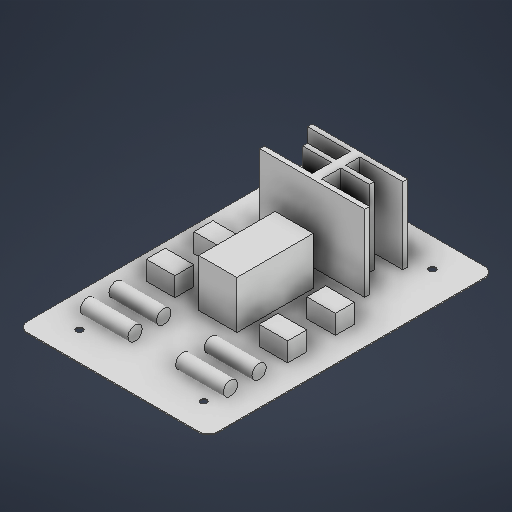
# Autodesk Inventor part: circuit_dummy
Saved by Autodesk Inventor 2027.1 (Build 311270010, 270A)
## iProperties
Created: 2026-10-24
Part Number: circuit_dummy
Material: Generic
Document SubType Name: Modeling
Designer: MSIPC
Density: 1 g/cm^3
Appearance: Default
Author: MSIPC
Autodesk Inventor part; units mm, degrees
ref_plane "YZ Plane" through (0, 0, 0) normal (1, 0, 0) x (0, 1, 0)
ref_plane "XZ Plane" through (0, 0, 0) normal (0, 1, 0) x (-1, 0, 0)
ref_plane "XY Plane" through (0, 0, 0) normal (0, 0, 1) x (1, 0, 0)
sketch "Sketch1" plane through (0, 0, 0) normal (0, 1, 0) x (-1, 0, 0)
  line L0 (-9, -15) -> (9, -15)
  line L1 (10, -14) -> (10, 14)
  line L2 (9, 15) -> (-9, 15)
  line L3 (-10, 14) -> (-10, -14)
  line L4 (-10, -15) -> (10, 15) construction
  line L5 (10, -15) -> (-10, 15) construction
  circle A0 centre (6.5, 12) radius 0.35
  line L6 (0, 0) -> (7.9497, 0)
  line L7 (0, 0) -> (0, 6.0781)
  circle A1 centre (6.5, -12) radius 0.35
  circle A2 centre (-6.5, 12) radius 0.35
  circle A3 centre (-6.5, -12) radius 0.35
  arc A4 (-9, 15) -> (-10, 14) centre (-9, 14) ccw
  arc A5 (10, 14) -> (9, 15) centre (9, 14) ccw
  arc A6 (9, -15) -> (10, -14) centre (9, -14) ccw
  arc A7 (-10, -14) -> (-9, -15) centre (-9, -14) ccw
  dimension "d0" = 30
  dimension "d1" = 20
  dimension "d2" = 0.7
  dimension "d3" = 6.5
  dimension "d4" = 12
  dimension "d7" = 1
  constraints: 16 end point, 8 centre point, 8 point on circle, 8 point on line, 8 tangent, 3 equal radius, 3 symmetric about line, 2 horizontal, 2 midpoint, 2 parallel, 1 perpendicular, 1 vertical, 3 other
  measures "d0" distance of L5.end L4.start
  measures "d1" distance of L4.start L5.start
  measures "d2" diameter of A0
  measures "d3" horizontal distance of A0.centre L6.start
  measures "d4" vertical distance of A0.centre L6.start
  measures "d7" radius of A4
extrude "Extrusion1" add sketch "Sketch1" along normal blind 0.1
sketch "Sketch2" plane through (0, 0.1, 0) normal (0, 1, 0) x (1, 0, 0)
  line L0 (9, 15) -> (-9, 15) projected
  line L1 (-10, 14) -> (-10, -14) projected
  line L2 (10, -14) -> (10, 14) projected
  line L3 (0, 10.8952) -> (-0.5, 10.8952)
  line L4 (-0.5, 5.8952) -> (0, 5.8952)
  line L5 (0, 10.8952) -> (-5, 10.8952)
  line L6 (-5, 10.8952) -> (-5, 10.3952)
  line L7 (-5, 10.3952) -> (-0.5, 10.3952)
  line L8 (-0.5, 8.3952) -> (-3.5, 8.3952)
  line L9 (-3.5, 8.3952) -> (-3.5, 8.8952)
  line L10 (-3.5, 8.8952) -> (-0.5, 8.8952)
  line L11 (-0.5, 5.8952) -> (-5.5, 5.8952)
  line L12 (-5.5, 5.8952) -> (-5.5, 6.3952)
  line L13 (-5.5, 6.3952) -> (-0.5, 6.3952)
  line L14 (0, 10.8952) -> (0.5, 10.8952)
  line L15 (0.5, 5.8952) -> (0, 5.8952)
  line L16 (0, 10.8952) -> (5, 10.8952)
  line L17 (5, 10.8952) -> (5, 10.3952)
  line L18 (5, 10.3952) -> (0.5, 10.3952)
  line L19 (0.5, 8.3952) -> (3.5, 8.3952)
  line L20 (3.5, 8.3952) -> (3.5, 8.8952)
  line L21 (3.5, 8.8952) -> (0.5, 8.8952)
  line L22 (0.5, 5.8952) -> (5.5, 5.8952)
  line L23 (5.5, 5.8952) -> (5.5, 6.3952)
  line L24 (5.5, 6.3952) -> (0.5, 6.3952)
  line L25 (-0.5, 10.3952) -> (-0.5, 8.8952)
  line L26 (-0.5, 8.3952) -> (-0.5, 6.3952)
  line L27 (0.5, 10.3952) -> (0.5, 8.8952)
  line L28 (0.5, 8.3952) -> (0.5, 6.3952)
  point P0 (0, 0)
  dimension "d12" = 0.5
  dimension "d13" = 5
  dimension "d15" = 0.5
  dimension "d16" = 3
  dimension "d17" = 0.5
  dimension "d18" = 5
  dimension "d19" = 0.5
  constraints: 52 end point, 5 perpendicular, 4 horizontal, 4 parallel
  measures "d12" distance of L4.end L4.start
  measures "d13" distance of L4.start L3.end
  measures "d15" distance of L6.end L5.end
  measures "d16" distance of L9.end L10.end
  measures "d17" distance of L8.end L9.end
  measures "d18" distance of L13.end L12.end
  measures "d19" distance of L11.end L12.end
extrude "Extrusion2" add sketch "Sketch2" along normal blind 8
sketch "Sketch3" plane through (0, 0.1, 0) normal (0, 1, 0) x (1, 0, 0)
  line L0 (-7.4165, 2.9034) -> (-4.4165, 2.9034)
  line L1 (-4.4165, 2.9034) -> (-4.4165, 0.9034)
  line L2 (-4.4165, 0.9034) -> (-7.4165, 0.9034)
  line L3 (-7.4165, 0.9034) -> (-7.4165, 2.9034)
  line L4 (0, 0) -> (0, -2.3619)
  line L5 (-7.4165, -2.0966) -> (-4.4165, -2.0966)
  line L6 (-4.4165, -2.0966) -> (-4.4165, -4.0966)
  line L7 (-4.4165, -4.0966) -> (-7.4165, -4.0966)
  line L8 (-7.4165, -4.0966) -> (-7.4165, -2.0966)
  line L9 (7.4165, 2.9034) -> (4.4165, 2.9034)
  line L10 (4.4165, 2.9034) -> (4.4165, 0.9034)
  line L11 (4.4165, 0.9034) -> (7.4165, 0.9034)
  line L12 (7.4165, 0.9034) -> (7.4165, 2.9034)
  line L13 (7.4165, -2.0966) -> (4.4165, -2.0966)
  line L14 (4.4165, -2.0966) -> (4.4165, -4.0966)
  line L15 (4.4165, -4.0966) -> (7.4165, -4.0966)
  line L16 (7.4165, -4.0966) -> (7.4165, -2.0966)
  dimension "d22" = 3
  dimension "d23" = 2
  dimension "d26" = 5
  constraints: 34 end point, 8 symmetric about line, 2 parallel, 2 vertical, 1 horizontal, 1 perpendicular, 8 other
  measures "d22" distance of L1.end L2.end
  measures "d23" distance of L0.end L1.end
  measures "d26" distance of L0.start L5.start
extrude "Extrusion3" add sketch "Sketch3" along normal blind 2
sketch "Sketch4" plane through (0, 0.1, 0) normal (0, 1, 0) x (1, 0, 0)
  line L0 (2, 4) -> (-2, 4)
  line L1 (-2, 4) -> (-2, -4)
  line L2 (-2, -4) -> (2, -4)
  line L3 (2, -4) -> (2, 4)
  line L4 (2, 4) -> (-2, -4) construction
  line L5 (-2, 4) -> (2, -4) construction
  point P0 (0, 0)
  dimension "d33" = 8
  dimension "d34" = 4
  constraints: 12 end point, 2 midpoint, 2 parallel, 1 horizontal, 1 perpendicular
  measures "d33" distance of L2.end L0.start
  measures "d34" distance of L0.start L0.end
extrude "Extrusion4" add sketch "Sketch4" along normal blind 5
sketch "Sketch5" plane through (7.4165, 0.1, 4.0966) normal (1, 0, 0) x (0, 0, -1)
  circle A0 centre (-3, 0.7) radius 0.75
  line L0 (0, 0) -> (0, 2) projected
  line L1 (2, 0) -> (0, 0) projected
  point P0 (4.0966, -0.1)
  point P1 (0, 1)
  dimension "d37" = 1.5
  dimension "d38" = 3
  dimension "d39" = 0.7
  constraints: 1 centre point, 1 midpoint
  measures "d37" diameter of A0
  measures "d38" horizontal distance of point (0, 1) A0.centre
  measures "d39" distance from line of L1 A0.centre
extrude "Extrusion5" add sketch "Sketch5" against normal blind 5
pattern_linear "Rectangular Pattern1" count 2 spacing 3 along (0, 0, 1) count 2 spacing 10 along (-1, 0, 0) of "Extrusion5"
body "Solid1"
